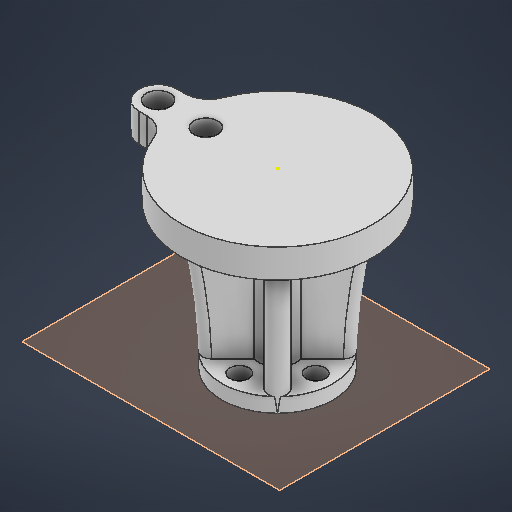
# Autodesk Inventor part: c1ipt
Saved by Autodesk Inventor 2026.2 (Build 302298010, 298A)
## iProperties
Created: 2026-04-03
Part Number: c1ipt
Material: 일반
Document SubType Name: Modeling
Designer: work
Density: 1 g/cm^3
Appearance: 기본값
Author: work
Autodesk Inventor part; units mm, degrees
ref_plane "YZ Plane" through (0, 0, 0) normal (1, 0, 0) x (0, 1, 0)
ref_plane "XZ Plane" through (0, 0, 0) normal (0, 1, 0) x (-1, 0, 0)
ref_plane "XY Plane" through (0, 0, 0) normal (0, 0, 1) x (1, 0, 0)
sketch "스케치1" plane through (0, 0, 0) normal (0, 1, 0) x (-1, 0, 0)
  circle A0 centre (0, 0) radius 15 construction
  circle A1 centre (0, 0) radius 20
  line L0 (0, 0) -> (15, 0) construction
  circle A2 centre (15, 0) radius 2
  circle A3 centre (0, 15) radius 2
  circle A4 centre (-15, 0) radius 2
  circle A5 centre (0, -15) radius 2
  dimension "d0" = 30
  dimension "d1" = 40
  dimension "d2" = 4
  dimension "d5" = 360
  constraints: 5 centre point, 3 coincident, 2 end point, 1 horizontal, 1 horizontal alignment, 11 other
  measures "d1" diameter of A1
  measures "d2" diameter of A2
extrude "돌출1" add sketch "스케치1" along normal blind 6
sketch "스케치2" plane through (0, 6, 0) normal (0, 1, 0) x (1, 0, 0)
  line L0 (0, 0) -> (-14.1421, 14.1421) construction
  circle A0 centre (0, 0) radius 20 projected
  line L1 (0, 0) -> (0, 15.1361) construction
  circle A1 centre (0, 0) radius 20 projected
  circle A2 centre (0, 15) radius 2 projected
  circle A3 centre (15, 0) radius 2 projected
  circle A4 centre (0, -15) radius 2 projected
  circle A5 centre (-15, 0) radius 2 projected
  line L2 (0, 0) -> (-15, 0) construction
  circle A6 centre (0, 0) radius 4
  line L3 (-3.8637, 1.0353) -> (-15.4855, 12.657)
  line L4 (-1.0353, 3.8637) -> (-12.657, 15.4855)
  line L5 (0, 0) -> (-14.1421, -14.1421) construction
  line L6 (-1.0353, -3.8637) -> (-12.657, -15.4855)
  line L7 (-3.8637, -1.0353) -> (-15.4855, -12.657)
  line L8 (0, 0) -> (14.1421, -14.1421) construction
  line L9 (3.8637, -1.0353) -> (15.4855, -12.657)
  line L10 (1.0353, -3.8637) -> (12.657, -15.4855)
  line L11 (0, 0) -> (14.1421, 14.1421) construction
  line L12 (1.0353, 3.8637) -> (12.657, 15.4855)
  line L13 (3.8637, 1.0353) -> (15.4855, 12.657)
  point P0 (-12.657, -15.4855)
  point P1 (12.657, -15.4855)
  point P2 (-15.4855, 12.657)
  dimension "d10" = 8
  dimension "d9" = 45
  dimension "d11" = 2
  dimension "d14" = 360
  constraints: 28 end point, 2 symmetric about line, 1 coincident, 1 horizontal, 1 parallel, 1 vertical, 44 other
  measures "d9" angle of L1 L0
  measures "d11" distance between parallel lines of L0 L3
extrude "돌출2" add sketch "스케치2" along normal blind 60 contours L13 A6 L12 A0 | A0 L10 A6 L9 | A6 | L4 A6 L3 A0 | A0 L7 A6 L6
sketch "스케치3" plane through (0, 66, 0) normal (0, 1, 0) x (1, 0, 0)
  circle A0 centre (0, 0) radius 20
  constraints: 1 centre point, 1 coincident
extrude "돌출3" add sketch "스케치3" along normal blind 6
sketch "스케치4" plane through (0, 72, 0) normal (0, 1, 0) x (1, 0, 0)
  point P0 (0, 0)
sketch "스케치5" plane through (0, 72, 0) normal (0, 1, 0) x (1, 0, 0)
  line L0 (-25, 0) -> (-15, 0) construction
  line L1 (-25, -4) -> (-15, -4)
  line L2 (-15, 4) -> (-25, 4)
  arc A0 (-25, 4) -> (-25, -4) centre (-25, 0) ccw
  arc A1 (-15, -4) -> (-15, 4) centre (-15, 0) ccw
  circle A2 centre (-15, 0) radius 2.5
  circle A3 centre (-25, 0) radius 2.5
  line L3 (-15, 0) -> (0, 0) construction
  point P0 (-20, 0)
  dimension "d21" = 8
  dimension "d22" = 10
  dimension "d23" = 5
  dimension "d24" = 5
  dimension "d25" = 15
  constraints: 10 end point, 4 centre point, 4 point on circle, 4 tangent, 2 coincident, 2 horizontal, 1 midpoint, 1 parallel
  measures "d21" diameter of A1
  measures "d22" distance of L0.start L0.end
  measures "d23" diameter of A2
  measures "d24" diameter of A3
  measures "d25" distance of L3.end L0.end
extrude "돌출4" add sketch "스케치5" against normal up to surface (6 mm away)
extrude "돌출5" cut sketch "스케치5" against normal up to surface (6 mm away) contours A2
fillet "모깎기1" radius 5 2 edges at (-19.5959, 69, 4) (-19.5959, 69, -4)
sketch "스케치6" plane through (0, 0, 0) normal (1, 0, 0) x (0, 1, 0)
  line L0 (6, -15.4855) -> (66, -15.4855) projected
  arc A0 (66, -15.4855) -> (6, -15.4855) centre (36, -131.675) ccw
  line L1 (0, 0) -> (72, 0)
  line L2 (72, -4) -> (72, 4) projected
  line L3 (66, -15.4855) -> (6, -15.4855)
  line L4 (6, -15.4855) -> (6, -44.0723)
  line L5 (6, -44.0723) -> (66, -44.0723)
  line L6 (66, -44.0723) -> (66, -15.4855)
  dimension "d31" = 120
  constraints: 10 end point, 2 parallel, 2 point on circle, 1 centre point, 1 horizontal, 1 midpoint, 1 perpendicular
  measures "d31" radius of A0
revolve "회전1" cut sketch "스케치6" angle 360 about axis through (0, 0, 0) along (0, 1, 0)
fillet "모깎기2" radius 2 8 edges at (9.5476, 36, 6.7192) (6.7192, 36, 9.5476) (9.5476, 36, -6.7192) (6.7192, 36, -9.5476) (-6.7192, 36, -9.5476) (-9.5476, 36, -6.7192) (-9.5476, 36, 6.7192) (-6.7192, 36, 9.5476)
chamfer "모따기1" distance 4 angle 45 8 edges at (0, 66, 4) (4, 66, 0) (0, 66, -4) (-4, 66, 0) (-4, 6, 0) (0, 6, -4) (4, 6, 0) (0, 6, 4)
ref_plane "작업 평면1" through (0, 36, 0) normal (0, 1, 0) x (1, 0, 0)
sketch "스케치7" plane through (0, 36, 0) normal (0, 1, 0) x (1, 0, 0)
  circle A0 centre (0, 0) radius 11.675
  arc A1 (-8.2554, -5.427) -> (-5.427, -8.2554) centre (-6.8412, -6.8412) ccw projected
  circle A2 centre (0, 8) radius 2
  arc A3 (4.063, 6.8914) -> (-4.063, 6.8914) centre (0, 0) ccw projected
  line L0 (0, 8) -> (0, 0) construction
  circle A4 centre (-8, 0) radius 2
  circle A5 centre (0, -8) radius 2
  circle A6 centre (8, 0) radius 2
  point P0 (-8.2554, -8.2554)
  dimension "d37" = 4
  dimension "d38" = 8
  dimension "d41" = 360
  constraints: 4 centre point, 2 end point, 1 coincident, 1 point on circle, 1 vertical, 12 other
  measures "d37" diameter of A2
  measures "d38" distance of point (0, 0) L0.start
extrude "돌출6" add sketch "스케치7" along normal mid plane 6
sketch "스케치8" plane through (0, 0, 0) normal (1, 0, 0) x (0, 1, 0)
  line L0 (36, 34.6338) -> (-22.9194, 34.6338)
  line L1 (-22.9194, 34.6338) -> (-22.9194, -45.0748)
  line L2 (-22.9194, -45.0748) -> (36, -45.0748)
  line L3 (36, -45.0748) -> (36, 34.6338)
  line L4 (0, -20) -> (0, 20) projected
  point P0 (0, 0)
  dimension "d45" = 36
  constraints: 8 end point, 2 parallel, 1 horizontal, 1 perpendicular
  measures "d45" distance between parallel lines of L3 L4
extrude "돌출7" cut sketch "스케치8" along normal through all both and the other way through all
